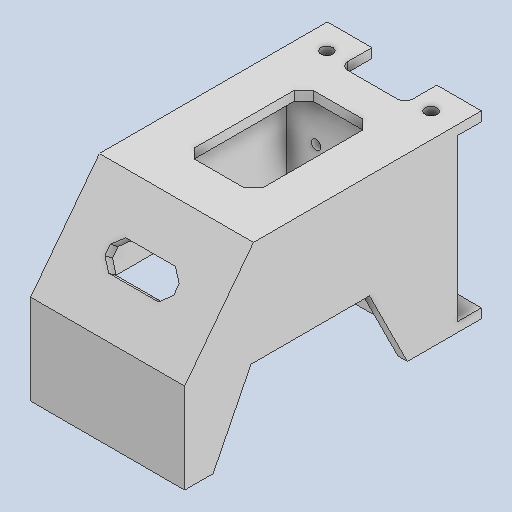
# Autodesk Inventor part: Fist
Saved by Autodesk Inventor 2025.2 (Build 292293000, 293)
## iProperties
Created: 2025-06-27
Part Number: Fist
Material: Generic
Document SubType Name: Modeling
Designer: ricoa
Density: 1 g/cm^3
Appearance: Default
Author: ricoa
Autodesk Inventor part; units mm, degrees
ref_plane "YZ Plane" through (0, 0, 0) normal (1, 0, 0) x (0, 1, 0)
ref_plane "XZ Plane" through (0, 0, 0) normal (0, 1, 0) x (-1, 0, 0)
ref_plane "XY Plane" through (0, 0, 0) normal (0, 0, 1) x (1, 0, 0)
sketch "Sketch1" plane through (0, 0, 0) normal (0, 0, 1) x (1, 0, 0)
  circle A0 centre (6.25, -2.5) radius 1 projected
  circle A1 centre (22.25, -2.5) radius 1 projected
  circle A2 centre (22.25, -14.5) radius 1 projected
  circle A3 centre (6.25, -14.5) radius 1 projected
  line L0 (26.3964, -25.5) -> (2.1036, -25.5) projected
  line L1 (28.5, 8.25) -> (28.5, 0.25) projected
  line L2 (28.5, -0.25) -> (28.5, -17) projected
  line L3 (0, -17) -> (0, -0.25) projected
  line L4 (2.1036, 8.5) -> (26.3964, 8.5) projected
  line L5 (28.5, -25.5) -> (0, -25.5)
  line L6 (0, -25.5) -> (0, 8.5)
  line L7 (0, 8.5) -> (28.5, 8.5)
  line L8 (28.5, 8.5) -> (28.5, -25.5)
  line L9 (-2, 10.5) -> (-2, -27.5)
  line L10 (-2, -27.5) -> (30.5, -27.5)
  line L11 (30.5, -27.5) -> (30.5, 10.5)
  line L12 (30.5, 10.5) -> (-2, 10.5)
  point P0 (0, 0)
  dimension "d2" = 2
  constraints: 16 end point, 4 parallel, 2 perpendicular, 1 horizontal, 3 other
  measures "d2" distance between parallel lines of L6 L9
extrude "Extrusion1" add sketch "Sketch1" along normal blind 2 contours L0 L5 L6 L3 L7 L4 L8 L1 L2 | L12 L11 L10 L9
sketch "Sketch2" plane through (-2, -27.5, 0) normal (-1, 0, 0) x (0, 0, 1)
  line L0 (54, 19) -> (41.0164, 36) projected
  line L1 (8, 2) -> (15, 16) projected
  line L2 (15, 16) -> (40, 16) projected
  line L3 (40, 16) -> (47, 2) projected
  line L4 (54, 19) -> (54, 2) projected
  line L5 (-3.6, 4) -> (-3.6, 34)
  line L6 (41.0164, 36) -> (39.4889, 38)
  line L7 (39.4889, 38) -> (2, 38)
  line L8 (2, 38) -> (-0.5328, 38)
  line L9 (-0.5328, 38) -> (-3.6, 38)
  line L10 (-3.6, 38) -> (-3.6, 34)
  line L11 (8, 2) -> (7, 0)
  line L12 (7, 0) -> (0, 0)
  line L13 (0, 0) -> (-3.6, 0)
  line L14 (-3.6, 4) -> (-3.6, 0)
  line L15 (47, 2) -> (48, 0)
  line L16 (48, 0) -> (54, 0)
  line L17 (54, 0) -> (54, 2)
  point P0 (2, 0)
  constraints: 26 end point, 4 perpendicular, 4 point on line, 2 horizontal, 1 vertical
extrude "Extrusion2" add sketch "Sketch2" against normal blind 2
sketch "Sketch3" plane through (30.5, -27.5, 0) normal (1, 0, 0) x (0, 0, -1)
  line L0 (-2, 38) -> (-2, 0) projected
  line L1 (-2, 38) -> (-39.4889, 38) projected
  line L2 (-39.4889, 38) -> (-54, 19) projected
  line L3 (-54, 19) -> (-54, 0) projected
  line L4 (-54, 0) -> (-48, 0) projected
  line L5 (-48, 0) -> (-40, 16) projected
  line L6 (-40, 16) -> (-15, 16) projected
  line L7 (-15, 16) -> (-7, 0) projected
  line L8 (-7, 0) -> (-2, 0) projected
  line L9 (0, 0) -> (0, 38) projected
  line L10 (0, 0) -> (3.6, 0) projected
  line L11 (3.6, 0) -> (3.6, 38) projected
  line L12 (3.6, 38) -> (0, 38) projected
  line L13 (0, 0) -> (0, 38) projected
  line L14 (0, 38) -> (-2, 38) projected
  line L15 (-2, 0) -> (-2, 38) projected
  line L16 (0, 0) -> (-2, 0) projected
  point P0 (0, 27.5)
extrude "Extrusion3" add sketch "Sketch3" against normal blind 2 contours L0 L8 L7 L6 L5 L4 L3 L2 L1 | L12 L11 L10 L9
chamfer "Chamfer1" distance 2 angle 45 1 edges at (0, -8.5, 0)
chamfer "Chamfer2" distance 2 angle 45 1 edges at (28.5, -8.5, 0)
sketch "Sketch4" plane through (28.5, -27.5, 0) normal (-1, 0, 0) x (0, 0, 1)
  line L0 (39.4889, 38) -> (2, 38) projected
  line L1 (54, 19) -> (39.4889, 38) projected
  line L2 (54, 0) -> (54, 19) projected
  line L3 (48, 0) -> (54, 0) projected
  line L4 (-3.6, 38) -> (39.4889, 38) projected
  line L5 (-3.6, 0) -> (7, 0) projected
  line L6 (0, 0) -> (0, 38) projected
  line L7 (38.4998, 36) -> (52, 18.3236)
  line L8 (52, 18.3236) -> (52, 2)
  line L9 (52, 2) -> (48, 2)
  line L10 (38.4998, 36) -> (2, 36)
  line L11 (-3.6, 2) -> (7, 2)
  line L12 (52, 2) -> (52, 0)
  line L13 (48, 0) -> (54, 0) projected
  line L14 (-3.6, 38) -> (-3.6, 0) projected
  line L15 (-3.6, 38) -> (-3.6, 36)
  line L16 (-3.6, 36) -> (0, 36)
  line L17 (0, 38) -> (0, 36)
  line L18 (-3.6, 36) -> (2, 36)
  line L19 (2, 0) -> (2, 38) projected
  line L20 (2, 0) -> (2, 2)
  point P0 (0, 27.5)
  point P1 (0, 2)
  dimension "d29" = 2
  dimension "d30" = 2
  dimension "d31" = 2
  constraints: 22 end point, 6 point on line, 3 perpendicular, 2 parallel, 1 other
  measures "d29" distance between parallel lines of L1 L7
  measures "d30" distance between parallel lines of L0 L10
  measures "d31" distance between parallel lines of L5 L11
extrude "Extrusion4" add sketch "Sketch4" along normal up to next contours L1 L2 L3 L12 L8 L7 L10 L19 L0 | L19 L18 L6 L4 | L6 L16 L14 L4 | L6 L5 L14 L11
sketch "Sketch5" plane through (-2, 10.5, 39.4889) normal (0, 1, 0) x (1, 0, 0)
  line L0 (32.5, 0) -> (0, 0) projected
  line L1 (32.5, 43.0889) -> (32.5, 0) projected
  line L2 (0, 43.0889) -> (32.5, 43.0889) projected
  line L3 (0, 43.0889) -> (0, 0) projected
  line L4 (21.5, 9) -> (11, 9)
  line L5 (9, 11) -> (9, 32.0889)
  line L6 (11, 34.0889) -> (21.5, 34.0889)
  line L7 (23.5, 32.0889) -> (23.5, 11)
  line L8 (9, 32.0889) -> (11, 34.0889)
  line L9 (21.5, 34.0889) -> (23.5, 32.0889)
  line L10 (9, 11) -> (11, 9)
  line L11 (21.5, 9) -> (23.5, 11)
  point P0 (2, 39.4889)
  point P1 (23.5, 9)
  point P2 (9, 9)
  point P3 (9, 34.0889)
  point P4 (23.5, 34.0889)
  dimension "d34" = 9
  dimension "d35" = 2
  dimension "d36" = 2
  dimension "d37" = 2
  dimension "d38" = 2
  dimension "d39" = 2
  dimension "d40" = 2
  dimension "d41" = 2
  dimension "d42" = 2
  constraints: 16 end point, 8 point on line, 3 other
  measures "d34" distance between parallel lines of L1 L7
  measures "d35" distance of L5.end point (9, 34.089)
  measures "d36" distance of L6.start point (9, 34.089)
  measures "d37" distance of L6.end point (23.5, 34.089)
  measures "d38" distance of L7.start point (23.5, 34.089)
  measures "d39" distance of L5.start point (9, 9)
  measures "d40" distance of L4.end point (9, 9)
  measures "d41" distance of L4.start point (23.5, 9)
  measures "d42" distance of L7.end point (23.5, 9)
extrude "Extrusion5" cut sketch "Sketch5" against normal blind 10 contours L4 L10 L5 L8 L6 L9 L7 L11
sketch "Sketch6" plane through (-2, 10.5, 39.4889) normal (0, 0.6069666, 0.7947273) x (1, 0, 0)
  line L0 (32.5, 0) -> (32.5, -23.9076) projected
  line L1 (32.5, 0) -> (0, 0) projected
  line L2 (0, -23.9076) -> (0, 0) projected
  line L3 (32.5, -23.9076) -> (0, -23.9076) projected
  line L4 (23.5, -12.9076) -> (23.5, -11)
  line L5 (21.5, -9) -> (11, -9)
  line L6 (9, -11) -> (9, -12.9076)
  line L7 (11, -14.9076) -> (21.5, -14.9076)
  line L8 (9, -11) -> (11, -9)
  line L9 (9, -12.9076) -> (11, -14.9076)
  line L10 (21.5, -14.9076) -> (23.5, -12.9076)
  line L11 (21.5, -9) -> (23.5, -11)
  point P0 (2, 15.6238)
  point P1 (23.5, -14.9076)
  point P2 (23.5, -9)
  point P3 (9, -9)
  point P4 (9, -14.9076)
  dimension "d45" = 9
  dimension "d46" = 2
  dimension "d47" = 2
  dimension "d48" = 2
  dimension "d49" = 2
  dimension "d50" = 2
  dimension "d51" = 2
  dimension "d52" = 2
  dimension "d53" = 2
  constraints: 16 end point, 8 point on line, 3 other
  measures "d45" distance between parallel lines of L0 L4
  measures "d46" distance of L6.start point (9, -9)
  measures "d47" distance of L5.end point (9, -9)
  measures "d48" distance of L6.end point (9, -14.908)
  measures "d49" distance of L7.start point (9, -14.908)
  measures "d50" distance of L7.end point (23.5, -14.908)
  measures "d51" distance of L4.start point (23.5, -14.908)
  measures "d52" distance of L5.start point (23.5, -9)
  measures "d53" distance of L4.end point (23.5, -9)
extrude "Extrusion6" cut sketch "Sketch6" against normal blind 10 contours L10 L7 L9 L6 L8 L5 L11 L4
sketch "Sketch7" plane through (-2, -27.5, -3.6) normal (0, 0, -1) x (-1, 0, 0)
  line L0 (-30.5, 2) -> (-2, 2) projected
  line L1 (-30.5, 36) -> (-30.5, 2) projected
  line L2 (-30.5, 36) -> (-2, 36) projected
  line L3 (-2, 2) -> (-2, 36) projected
  line L4 (0, 38) -> (0, 0) projected
  line L5 (0, 38) -> (-32.5, 38) projected
  line L6 (-32.5, 0) -> (-32.5, 38) projected
  line L7 (-32.5, 0) -> (0, 0) projected
  line L8 (-2, 36) -> (0, 36)
  line L9 (-30.5, 36) -> (-32.5, 36)
  line L10 (-32.5, 2) -> (0, 2)
  point P0 (-2, 27.5)
  constraints: 6 end point, 6 point on line, 1 perpendicular
extrude "Extrusion7" add sketch "Sketch7" along normal blind 5 contours L0 L10 L4 L7 L6 | L9 L6 L5 L4 L8 L2
sketch "Sketch8" plane through (-2, 10.5, 39.4889) normal (0, 1, 0) x (1, 0, 0)
  circle A0 centre (5.25, 42.7389) radius 2.5 projected
  circle A1 centre (27.25, 42.7389) radius 2.5 projected
  arc A2 (23, 47.9889) -> (21.5, 49.4889) centre (21.5, 47.9889) ccw projected
  line L0 (21.5, 49.4889) -> (11, 49.4889) projected
  arc A3 (11, 49.4889) -> (9.5, 47.9889) centre (11, 47.9889) ccw projected
  line L1 (9.5, 47.9889) -> (9.5, 42.9889) projected
  arc A4 (9.5, 42.9889) -> (11, 41.4889) centre (11, 42.9889) ccw projected
  line L2 (11, 41.4889) -> (21.5, 41.4889) projected
  arc A5 (21.5, 41.4889) -> (23, 42.9889) centre (21.5, 42.9889) ccw projected
  line L3 (23, 42.9889) -> (23, 47.9889) projected
  circle A6 centre (5.25, 42.7389) radius 1.25
  circle A7 centre (27.25, 42.7389) radius 1.25
  point P0 (2, 39.4889)
  dimension "d58" = 2.5
  dimension "d59" = 2.5
  constraints: 2 centre point, 2 coincident
  measures "d58" diameter of A6
  measures "d59" diameter of A7
extrude "Extrusion8" cut sketch "Sketch8" against normal through all contours A6 | A7
sketch "Sketch9" plane through (-2, 10.5, 39.4889) normal (0, 1, 0) x (1, 0, 0)
  arc A0 (23, 47.9889) -> (21.5, 49.4889) centre (21.5, 47.9889) ccw projected
  line L0 (21.5, 49.4889) -> (11, 49.4889) projected
  arc A1 (11, 49.4889) -> (9.5, 47.9889) centre (11, 47.9889) ccw projected
  line L1 (9.5, 47.9889) -> (9.5, 42.9889) projected
  arc A2 (9.5, 42.9889) -> (11, 41.4889) centre (11, 42.9889) ccw projected
  line L2 (11, 41.4889) -> (21.5, 41.4889) projected
  arc A3 (21.5, 41.4889) -> (23, 42.9889) centre (21.5, 42.9889) ccw projected
  line L3 (23, 42.9889) -> (23, 47.9889) projected
  line L4 (21.5, 41.3889) -> (11, 41.3889)
  arc A4 (9.4, 42.9889) -> (11, 41.3889) centre (11, 42.9889) ccw
  line L5 (9.4, 42.9889) -> (9.4, 47.9889)
  arc A5 (11, 49.5889) -> (9.4, 47.9889) centre (11, 47.9889) ccw
  line L6 (11, 49.5889) -> (21.5, 49.5889)
  arc A6 (23.1, 47.9889) -> (21.5, 49.5889) centre (21.5, 47.9889) ccw
  line L7 (23.1, 47.9889) -> (23.1, 42.9889)
  arc A7 (21.5, 41.3889) -> (23.1, 42.9889) centre (21.5, 42.9889) ccw
  point P0 (2, 39.4889)
  dimension "d62" = 0.1
  constraints: 8 end point, 8 point on circle, 4 centre point, 7 other
  measures "d62" distance between parallel lines of L2 L4
extrude "Extrusion9" cut sketch "Sketch9" against normal blind 10 contours L3 A3 L2 A2 L1 A1 L0 A0 | L4 A4 L5 A5 L6 A6 L7 A7
equation "\"d36\" = d35"
equation "\"d37\" = d35"
equation "\"d38\" = d37"
equation "\"d39\" = d35"
equation "\"d40\" = d39"
equation "\"d41\" = d35"
equation "\"d42\" = d41"
equation "\"d47\" = d46"
equation "\"d48\" = d46"
equation "\"d49\" = d48"
equation "\"d50\" = d46"
equation "\"d51\" = d50"
equation "\"d52\" = d46"
equation "\"d53\" = d52"
body "Solid1"
